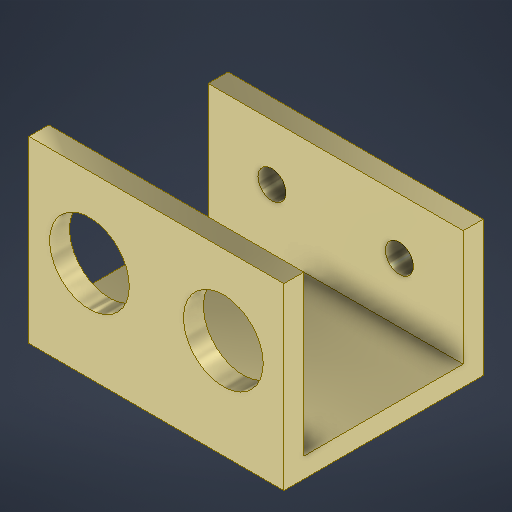
# Autodesk Inventor part: s1101mfa1805
Saved by Autodesk Inventor 2027.1 (Build 311270010, 270A)
## iProperties
Created: 2026-10-31
Part Number: s1101mfa1805
Material: Generic
Document SubType Name: Modeling
Designer: User
Density: 1 g/cm^3
Appearance: Gold - Metal
Author: User
Autodesk Inventor part; units mm, degrees
ref_plane "YZ Plane" through (0, 0, 0) normal (1, 0, 0) x (0, 1, 0)
ref_plane "XZ Plane" through (0, 0, 0) normal (0, 1, 0) x (-1, 0, 0)
sketch "Sketch1" plane through (0, 0, 0) normal (1, 0, 0) x (0, 1, 0)
  line L0 (0, 0) -> (21.59, 0)
  line L1 (21.59, 0) -> (21.59, 3.175)
  line L2 (21.59, 3.175) -> (3.175, 3.175)
  line L3 (3.175, 3.175) -> (3.175, 28.575)
  line L4 (3.175, 28.575) -> (28.575, 28.575)
  line L5 (28.575, 28.575) -> (28.575, 31.75)
  line L6 (28.575, 31.75) -> (0, 31.75)
  line L7 (0, 31.75) -> (0, 0)
  constraints: 16 end point
extrude "Extrusion1" add sketch "Sketch1" along normal mid plane 40.64
sketch "Sketch2" plane through (0, 0, 0) normal (0, 0, 1) x (1, 0, 0)
  circle A0 centre (-10.16, 12.7) radius 2.2352
  circle A1 centre (10.16, 12.7) radius 2.2352
  constraints: 2 centre point
extrude "Extrusion2" cut sketch "Sketch2" along normal mid plane 7.62
ref_plane "Work Plane1" through (0, 0, 31.75) normal (0, 0, 1) x (1, 0, 0)
sketch "Sketch3" plane through (0, 0, 31.75) normal (0, 0, 1) x (1, 0, 0)
  circle A0 centre (-10.668, 15.875) radius 6.35
  circle A1 centre (10.668, 15.875) radius 6.35
  constraints: 2 centre point
extrude "Extrusion3" cut sketch "Sketch3" along normal mid plane 7.62
body "Solid1"
